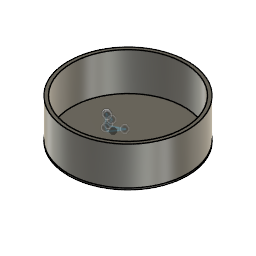
CASA0021 (Autodesk Fusion 360 design; units mm, degrees)
part number: 2026-03-04-22-03-16-966
Autodesk Fusion 360 part; units mm, degrees
sketch "草图1" plane through (0, 0, 0) normal (0, 0, 1) x (1, 0, 0)
  circle A0 centre (0, 0) radius 34
  circle A1 centre (0, 0) radius 34
  dimension "d1" = 68
  dimension "d2" = 0
  constraint coincident A0.centre A1.centre
  measures "d1" diameter of A0
extrude "拉伸1" add sketch "草图1" along normal blind 1 makes body 1
sketch "草图2" plane through (0, 0, 1) normal (0, 0, 1) x (-1, 0, 0)
  circle A0 centre (0, 0) radius 34
  circle A1 centre (0, 0) radius 36
  dimension "d5" = 2
extrude "拉伸2" add sketch "草图2" along normal blind 23 separate body makes body 2
move_face "偏移面1" offset 2 1 faces at (-33.9577, 1.6948, 0.3333) on bodies 1
sketch "草图4" plane through (0, 0, 0) normal (0, 1, 0) x (1, 0, 0)
  circle A0 centre (0, 10) radius 20
  line L0 (-20, 0) -> (-20, 10)
  line L1 (-20, 10) -> (20, 10)
  line L2 (20, -0.0351) -> (20, 10)
  dimension "d11" = 40
  constraint vertical L0
  constraint coincident A0 L1.end
  constraint perpendicular L0 L1
  constraint perpendicular L1 L2
  measures "d11" diameter of A0
sketch "草图5" plane through (0, 0, 0) normal (0, 0, 1) x (1, 0, 0)
  line L0 (-17, -8) -> (-23, -8)
  line L1 (-23, -8) -> (-23, 8)
  line L2 (-23, 8) -> (-17, 8)
  line L3 (-17, 8) -> (-17, -8)
  line L4 (-17, -8) -> (-23, 8) construction
  line L5 (-23, -8) -> (-17, 8) construction
  line L6 (23, -8) -> (17, -8)
  line L7 (17, -8) -> (17, 8)
  line L8 (17, 8) -> (23, 8)
  line L9 (23, 8) -> (23, -8)
  line L10 (23, -8) -> (17, 8) construction
  line L11 (17, -8) -> (23, 8) construction
  point P0 (-20, 0)
  point P1 (20, 0)
  constraint horizontal L0
  constraint perpendicular L0 L1
  constraint parallel L0 L2
  constraint parallel L1 L3
  constraint coincident L4 P0
  constraint coincident L5 P0
  constraint horizontal L6
  constraint perpendicular L6 L7
  constraint parallel L6 L8
  constraint parallel L7 L9
  constraint coincident L10 P1
  constraint coincident L11 P1
extrude "拉伸4" add sketch "草图5" against normal blind 10 separate body contours L0 L1 L2 L3 makes body 3
extrude "拉伸5" add sketch "草图5" against normal blind 10 separate body contours L6 L7 L8 L9 makes body 4
fillet "圆角1" radius 3 1 edges at (-23, 0, -10) on bodies 3
fillet "圆角2" radius 3 1 edges at (-17, 0, -10) on bodies 3
fillet "圆角3" radius 3 1 edges at (17, 0, -10) on bodies 4
fillet "圆角4" radius 3 1 edges at (23, 0, -10) on bodies 4
sketch "草图6" plane through (0, 8, 0) normal (0, 1, 0) x (-1, 0, 0)
  arc A0 (-23, -7) -> (-20, -10) centre (-20, -7) ccw
  arc A1 (-20, -10) -> (-17, -7) centre (-20, -7) ccw
  line L0 (-17, -7) -> (-17, 0)
  line L1 (-17, 0) -> (-23, 0)
  line L2 (-23, 0) -> (-23, -7)
  spline S0 degree 5 poles (-21, 0) (-21.1739, 0) (-21.4896, -0.1094) (-21.8546, -0.6319) (-22.0986, -2.08) (-22.0232, -4.5402) (-21.6406, -6.8693) (-21.0222, -8.3841) (-20.2274, -8.7311) (-19.1911, -8.5145) (-18.0846, -8.0114) (-17.1889, -7.2492) (-16.7787, -6.172) (-16.9851, -4.768) (-17.7333, -3.1665) (-18.8336, -1.5774) (-19.7938, -0.5716) (-20.4465, -0.1094) (-20.8261, 0) (-21, 0) knots 0 0 0 0 0 0 0.066667 0.133333 0.2 0.266667 0.333333 0.4 0.466667 0.533333 0.6 0.666667 0.733333 0.8 0.866667 0.933333 1 1 1 1 1 1
  line L3 (-21.1834, -8.196) -> (-19.8166, -8.804)
  line L4 (-20.5, 0) -> (-21.5, 0)
  point P0 (-20.5, -8.5)
  point P1 (-17, -6.5)
  constraint coincident L1 S0.start
  constraint coincident L0 P1
  constraint midpoint P0 L3
  constraint midpoint S0.start L4
  constraint coincident L1 L4.start
extrude "拉伸6" cut sketch "草图6" against normal blind 18.5 contours L0 L1 S0 L4 bodies 4
extrude "拉伸7" cut sketch "草图6" against normal blind 25.5 contours L0 S0 picked at (-18.7686, -6.397) bodies 4
sketch "草图7" plane through (0, 8, 0) normal (0, 1, 0) x (-1, 0, 0)
  arc A0 (17, -7) -> (20, -10) centre (20, -7) ccw
  arc A1 (20, -10) -> (23, -7) centre (20, -7) ccw
  line L0 (23, -7) -> (23, 0)
  line L1 (23, 0) -> (17, 0)
  line L2 (17, 0) -> (17, -7)
  spline S0 degree 5 poles (21, 0) (21.0038, -0.0219) (21.0055, -0.1152) (21.0067, -0.4222) (21.0497, -1.1927) (21.1951, -2.6481) (21.3908, -4.3723) (21.552, -6.0861) (21.573, -7.515) (21.3473, -8.4474) (20.7905, -8.7988) (19.8512, -8.5899) (18.523, -7.916) (16.8555, -6.9203) (14.9673, -5.7656) (13.0541, -4.6085) (11.3487, -3.5908) (10.0859, -2.8293) (9.466, -2.4064) (9.6166, -2.3596) (10.5599, -2.6727) (12.1641, -3.2614) (14.1747, -3.9894) (16.2754, -4.6969) (18.1397, -5.2252) (19.4843, -5.4416) (20.1265, -5.2667) (20.0299, -4.6962) (19.3816, -3.8375) (18.5372, -2.8802) (17.8848, -2.024) (17.7353, -1.4208) (18.1981, -1.1084) (19.0722, -0.9536) (20.0174, -0.775) (20.7027, -0.4487) (20.9287, -0.1228) (20.9828, 0.0161) (20.9962, 0.0219) (21, 0) knots 0 0 0 0 0 0 0.028571 0.057143 0.085714 0.114286 0.142857 0.171429 0.2 0.228571 0.257143 0.285714 0.314286 0.342857 0.371429 0.4 0.428571 0.457143 0.485714 0.514286 0.542857 0.571429 0.6 0.628571 0.657143 0.685714 0.714286 0.742857 0.771429 0.8 0.828571 0.857143 0.885714 0.914286 0.942857 0.971429 1 1 1 1 1 1
  point P0 (21.5, -7.5)
  point P1 (17, -7)
  point P2 (10, -2.5)
  point P3 (20, -5)
  point P4 (17.8787, -1.5161)
  point P5 (20.5, -0.5)
  constraint coincident L1 S0.start
  constraint coincident A0.start L2.end
extrude "拉伸8" cut sketch "草图7" against normal blind 22.5 contours L1 L2 S0 picked at (17.9381, -4.1689) bodies 3
extrude "拉伸9" cut sketch "草图7" against normal blind 21 contours L1 L2 S0 picked at (19.8207, -1.9945) bodies 3
